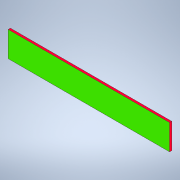
# Autodesk Inventor part: laterala_dreapta
Saved by Autodesk Inventor 2022.6 (Build 266554000, 554)
## iProperties
Created: 2025-04-03
Part Number: laterala_dreapta
Material: Generic
Document SubType Name: Modeling
Designer: Dragos Macovei
Density: 1 g/cm^3
Appearance: Default
Author: Dragos Macovei
Autodesk Inventor part; units mm, degrees
ref_plane "YZ Plane" through (0, 0, 0) normal (1, 0, 0) x (0, 1, 0)
ref_plane "XZ Plane" through (0, 0, 0) normal (0, 1, 0) x (-1, 0, 0)
ref_plane "XY Plane" through (0, 0, 0) normal (0, 0, 1) x (1, 0, 0)
sketch "Sketch1" plane through (0, 0, 0) normal (0, 0, 1) x (1, 0, 0)
  line L0 (0, 0) -> (1296, 0)
  line L1 (1296, 0) -> (1296, 200)
  line L2 (1296, 200) -> (0, 200)
  line L3 (0, 200) -> (0, 0)
  dimension "d8" = 200
  dimension "d9" = 1296
  constraints: 8 end point, 2 parallel, 1 horizontal, 1 perpendicular
  measures "d8" distance between parallel lines of L0 L2
  measures "d9" distance between parallel lines of L1 L3
extrude "PAL" add sketch "Sketch1" along normal blind 18
sketch "Sketch2" plane through (0, 0, 18) normal (0, 0, 1) x (1, 0, 0)
  line L0 (1296, 0) -> (1296, 200) projected
  line L1 (1296, 200) -> (0, 200) projected
  line L2 (0, 200) -> (0, 0) projected
  line L3 (0, 0) -> (1296, 0) projected
  line L4 (-2, 202) -> (1298, 202)
  line L5 (1298, 202) -> (1298, -2)
  line L6 (1298, -2) -> (-2, -2)
  line L7 (-2, -2) -> (-2, 202)
  dimension "d2" = 2
  dimension "d3" = 2
  dimension "d4" = 2
  dimension "d5" = 2
  constraints: 8 end point, 2 parallel, 1 horizontal, 1 perpendicular
  measures "d2" distance between parallel lines of L1 L4
  measures "d3" distance between parallel lines of L3 L6
  measures "d4" distance between parallel lines of L2 L7
  measures "d5" distance between parallel lines of L0 L5
extrude "Cant 4x2" add sketch "Sketch2" against normal up to surface (18 mm away)
body "Solid1"
